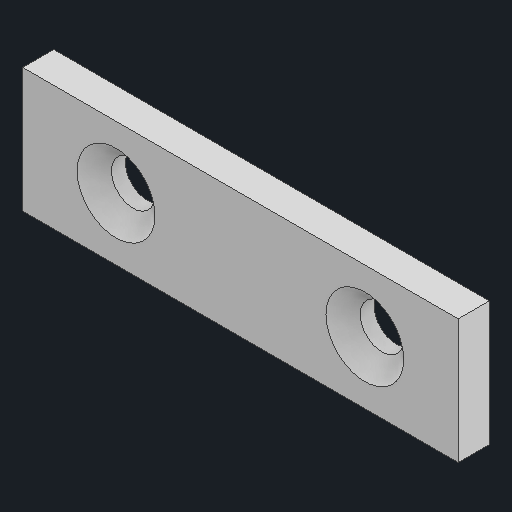
# Autodesk Inventor part: P4-03 Pad carrier
Saved by Autodesk Inventor 2027.1 (Build 311270010, 270A)
## iProperties
Created: 2026-10-21
Part Number: P4-03 Pad carrier
Material: Generic
Document SubType Name: Modeling
Designer: anshi
Mass: 0.409939 g
Surface Area: 5.94369 cm^2
Volume: 0.409939 cm^3
Density: 1 g/cm^3
Appearance: Default
Author: anshi
Autodesk Inventor part; units mm, degrees
ref_plane "Work Plane1" through (0, 0, 2) normal (0, 0, 1) x (1, 0, 0)
sketch "Dimensioned base profile" plane through (0, 0, 0) normal (0, 0, 1) x (1, 0, 0)
  line L0 (0, 0) -> (28, 0)
  line L1 (28, 0) -> (28, 8)
  line L2 (28, 8) -> (0, 8)
  line L3 (0, 8) -> (0, 0)
  constraints: 8 end point
extrude "Thickness 2 mm" add sketch "Dimensioned base profile" along normal blind 2
ref_plane "Work Plane2" through (0, 0, 2) normal (0, 0, 1) x (1, 0, 0)
sketch "Through-hole circles" plane through (0, 0, 2) normal (0, 0, 1) x (1, 0, 0)
  circle A0 centre (6, 4) radius 1.4
  circle A1 centre (22, 4) radius 1.4
  constraints: 2 centre point
extrude "Through holes" cut sketch "Through-hole circles" against normal blind 2
ref_plane "Work Plane3" through (0, 0, 2) normal (0, 0, 1) x (1, 0, 0)
sketch "CSK top 1" plane through (0, 0, 2) normal (0, 0, 1) x (1, 0, 0)
  circle A0 centre (6, 4) radius 2.5
  constraints: 1 centre point
ref_plane "Work Plane4" through (0, 0, 0.9) normal (0, 0, 1) x (1, 0, 0)
sketch "CSK neck 1" plane through (0, 0, 0.9) normal (0, 0, 1) x (1, 0, 0)
  circle A0 centre (6, 4) radius 1.4
  constraints: 1 centre point
loft "90deg countersink 1" cut profiles "CSK top 1", "CSK neck 1"
ref_plane "Work Plane5" through (0, 0, 2) normal (0, 0, 1) x (1, 0, 0)
sketch "CSK top 2" plane through (0, 0, 2) normal (0, 0, 1) x (1, 0, 0)
  circle A0 centre (22, 4) radius 2.5
  constraints: 1 centre point
ref_plane "Work Plane6" through (0, 0, 0.9) normal (0, 0, 1) x (1, 0, 0)
sketch "CSK neck 2" plane through (0, 0, 0.9) normal (0, 0, 1) x (1, 0, 0)
  circle A0 centre (22, 4) radius 1.4
  constraints: 1 centre point
loft "90deg countersink 2" cut profiles "CSK top 2", "CSK neck 2"
equation "\"NominalThickness\" = 2"
body "Solid2"
